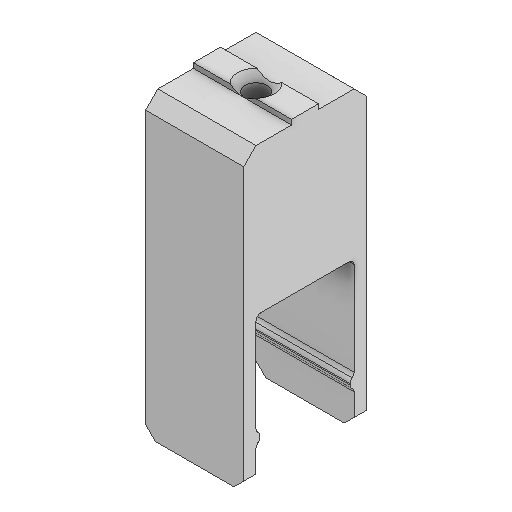
# Autodesk Inventor part: 3DP_PLA_Folded_Leg_Holder_REVB
Saved by Autodesk Inventor 2027 (Build 310192060, 192F)
## iProperties
Created: 2026-03-01
Part Number: 3DP_PLA_Folded_Leg_Holder_REVB
Material: Generic
Document SubType Name: Modeling
Designer: User
Density: 1 g/cm^3
Appearance: Default
Author: User
Autodesk Inventor part; units mm, degrees
ref_plane "YZ Plane" through (0, 0, 0) normal (1, 0, 0) x (0, 1, 0)
ref_plane "XZ Plane" through (0, 0, 0) normal (0, 1, 0) x (-1, 0, 0)
ref_plane "XY Plane" through (0, 0, 0) normal (0, 0, 1) x (1, 0, 0)
sketch "Sketch1" plane through (0, 0, 0) normal (0, 1, 0) x (-1, 0, 0)
  line L0 (10, 10) -> (-10, 10)
  line L1 (-10, 10) -> (-10, -10)
  line L2 (-10, -10) -> (10, -10)
  line L3 (10, -10) -> (10, 10)
  line L4 (10, 10) -> (10, 12.5)
  line L5 (10, 12.5) -> (-10, 12.5)
  line L6 (-10, 12.5) -> (-10, 10)
  line L7 (10, -10) -> (10, -12.5)
  line L8 (10, -12.5) -> (-10, -12.5)
  line L9 (-10, -12.5) -> (-10, -10)
  point P0 (0, 0)
  point P1 (0, 0)
  dimension "d0" = 20
  dimension "d1" = 20
  dimension "d2" = 10
  dimension "d3" = 10
  dimension "d6" = 2.5
  dimension "d7" = 2.5
  constraints: 20 end point, 5 perpendicular, 2 parallel, 2 vertical, 1 coincident, 1 horizontal
  measures "d0" distance of L2.end L0.start
  measures "d1" distance of L0.start L0.end
  measures "d2" distance from line of L0 point (0, 0)
  measures "d3" distance from line of point (0, 0) L3
  measures "d6" distance of L0.start L4.end
  measures "d7" distance of L2.end L7.end
extrude "Extrusion1" add sketch "Sketch1" along normal blind 30
extrude "Extrusion2" add sketch "Sketch1" against normal blind 30 contours L0 L6 L5 L4 | L7 L8 L9 L2
sketch "Sketch2" plane through (-10, 30, -12.5) normal (-1, 0, 0) x (0, 0, 1)
  line L0 (2.5, -30) -> (22.5, -30) projected
  line L1 (22.5, -30) -> (22.5, -60) projected
  line L2 (25, -60) -> (22.5, -60) projected
  line L3 (25, -60) -> (25, 0) projected
  line L4 (0, 0) -> (25, 0) projected
  line L5 (0, -60) -> (0, 0) projected
  line L6 (2.5, -60) -> (0, -60) projected
  line L7 (2.5, -30) -> (2.5, -60) projected
  line L8 (2.5, -52.5) -> (3.3, -52.5)
  line L9 (3.3, -52.5) -> (3.3, -51)
  line L10 (3.3, -51) -> (2.5, -51)
  line L11 (22.5, -51) -> (21.7, -51)
  line L12 (21.7, -51) -> (21.7, -52.5)
  line L13 (21.7, -52.5) -> (22.5, -52.5)
  point P0 (12.5, -30)
  dimension "d10" = 1.5
  dimension "d11" = 0.8
  dimension "d12" = 21
  dimension "d13" = 1.5
  dimension "d14" = 0.8
  dimension "d15" = 21
  constraints: 12 end point, 4 perpendicular, 4 point on line, 2 horizontal
  measures "d10" distance of L8.end L9.end
  measures "d11" distance of L8.start L8.end
  measures "d12" distance between parallel lines of L0 L10
  measures "d13" distance of L11.end L12.end
  measures "d14" distance of L12.end L13.end
  measures "d15" distance between parallel lines of L0 L11
extrude "Extrusion3" add sketch "Sketch2" against normal up to surface (20 mm away) contours L10 L9 L8 L7 | L1 L13 L12 L11
fillet "Fillet1" radius 1 8 edges at (0, -22.5, -9.2) (0, -21, -9.2) (0, -22.5, -10) (0, -21, -10) (0, -22.5, 10) (0, -22.5, 9.2) (0, -21, 9.2) (0, -21, 10)
fillet "Fillet2" radius 1 2 edges at (0, 0, -10) (0, 0, 10)
hole "Hole1" at (0, 0, 0) direction (0, 1, 0) diameter 10 depth 18
chamfer "Chamfer1" distance 2 angle 45 4 edges at (-10, -30, -11.25) (10, -30, -11.25) (10, -30, 11.25) (-10, -30, 11.25)
sketch "Sketch3" plane through (-10, 30, -12.5) normal (-1, 0, 0) x (0, 0, 1)
  line L0 (0, 0) -> (25, 0) projected
  line L1 (25, -58) -> (25, 0) projected
  line L2 (0, -58) -> (0, 0) projected
  line L3 (9.75, 0) -> (9.75, 1)
  line L4 (9.75, 1) -> (15.25, 1)
  line L5 (15.25, 1) -> (15.25, 0)
  point P0 (12.5, -30)
  dimension "d38" = 25
  dimension "d40" = 5.5
  dimension "d41" = 9.75
  dimension "d42" = 1
  constraints: 6 end point, 2 perpendicular, 2 point on line, 1 vertical
  measures "d38" distance between parallel lines of L1 L2
  measures "d40" distance of L3.end L4.end
  measures "d41" distance between parallel lines of L2 L3
  measures "d42" distance of L4.end L5.end
extrude "Extrusion4" add sketch "Sketch3" against normal up to surface (20 mm away)
hole "Hole2" at (0, 0, 0) direction (0, 1, 0) diameter 4.5 end through all
chamfer "Chamfer2" distance 1.5 angle 45 1 edges at (0, 31, 2.25)
chamfer "Chamfer3" distance 2.5 angle 45 2 edges at (0, 30, 12.5) (0, 30, -12.5)
equation "\"d1\" = d0"
equation "\"d2\" = 0.5 * d0"
equation "\"d3\" = 0.5 * d1"
equation "\"d7\" = d6"
equation "\"d14\" = d11"
equation "\"d15\" = d12"
equation "\"d41\" = -0.5 * d40 + 0.5 * d38"
body "Solid1"
